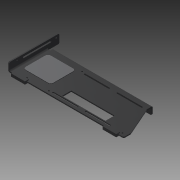
# Autodesk Inventor part: foot_plate
Saved by Autodesk Inventor 2015 (Build 190159000, 159)
## iProperties
Created: 2022-11-07
Part Number: foot_plate
Material: Generic
Document SubType Name: Modeling
Designer: Pavel Brodský
Density: 1 g/cm^3
Appearance: Default
Author: Pavel Brodský
Autodesk Inventor part; units mm, degrees
ref_plane "YZ Plane" through (0, 0, 0) normal (1, 0, 0) x (0, 1, 0)
ref_plane "XZ Plane" through (0, 0, 0) normal (0, 1, 0) x (-1, 0, 0)
ref_plane "XY Plane" through (0, 0, 0) normal (0, 0, 1) x (1, 0, 0)
sketch "Náčrt1" plane through (0, 0, 0) normal (0, 0, 1) x (1, 0, 0)
  line L0 (0, 0) -> (9, 0)
  line L1 (9, 0) -> (9, 12)
  line L2 (9, 12) -> (367, 12)
  line L3 (367, 12) -> (367, -10)
  line L4 (367, -10) -> (412, -113)
  line L5 (412, -113) -> (412, -138)
  line L6 (412, -138) -> (0, -138)
  line L7 (0, -138) -> (0, 0)
  arc A0 (145, -123) -> (145, -128) centre (145, -125.5) ccw
  arc A1 (233, -128) -> (233, -123) centre (233, -125.5) ccw
  line L8 (145, -123) -> (233, -123)
  line L9 (145, -128) -> (233, -128)
  arc A2 (263, -123) -> (263, -128) centre (263, -125.5) ccw
  arc A3 (351, -128) -> (351, -123) centre (351, -125.5) ccw
  line L10 (263, -123) -> (351, -123)
  line L11 (263, -128) -> (351, -128)
  arc A4 (145, -9) -> (145, -14) centre (145, -11.5) ccw
  arc A5 (233, -14) -> (233, -9) centre (233, -11.5) ccw
  line L12 (145, -9) -> (233, -9)
  line L13 (145, -14) -> (233, -14)
  arc A6 (263, -9) -> (263, -14) centre (263, -11.5) ccw
  arc A7 (351, -14) -> (351, -9) centre (351, -11.5) ccw
  line L14 (263, -9) -> (351, -9)
  line L15 (263, -14) -> (351, -14)
  line L16 (174, -86.99) -> (326, -86.99)
  line L17 (328, -88.99) -> (328, -117.99)
  line L18 (326, -119.99) -> (174, -119.99)
  line L19 (172, -117.99) -> (172, -88.99)
  circle A8 centre (397, -127) radius 2.5
  circle A9 centre (52.5, -127) radius 2.5
  circle A10 centre (132.5, -8) radius 2.5
  circle A11 centre (132.5, -128) radius 2.5
  arc A12 (174, -86.99) -> (172, -88.99) centre (174, -88.99) ccw
  arc A13 (172, -117.99) -> (174, -119.99) centre (174, -117.99) ccw
  arc A14 (328, -88.99) -> (326, -86.99) centre (326, -88.99) ccw
  arc A15 (326, -119.99) -> (328, -117.99) centre (326, -117.99) ccw
  point P0 (172, -86.99)
  point P1 (328, -86.99)
  dimension "d0" = 358
  dimension "d1" = 22
  dimension "d2" = 150
  dimension "d3" = 412
  dimension "d4" = 9
  dimension "d5" = 12
  dimension "d6" = 25
  dimension "d7" = 5
  dimension "d8" = 5
  dimension "d9" = 88
  dimension "d10" = 135
  dimension "d13" = 118
  dimension "d16" = 114
  dimension "d19" = 16
  dimension "d20" = 156
  dimension "d21" = 33
  dimension "d22" = 5.51
  dimension "d23" = 84
  dimension "d24" = 5
  dimension "d25" = 15
  dimension "d26" = 11
  dimension "d27" = 5
  dimension "d28" = 11
  dimension "d29" = 92.5
  dimension "d30" = 5
  dimension "d31" = 5
  dimension "d32" = 120
  dimension "d33" = 10
  dimension "d34" = 80
  dimension "d35" = 2
  constraints: 40 end point, 24 point on circle, 16 centre point, 11 tangent, 6 perpendicular, 4 point on line, 3 equal radius, 3 horizontal, 3 parallel, 1 collinear, 1 horizontal alignment, 1 vertical, 1 vertical alignment, 29 other
  measures "d0" distance of L1.end L2.end
  measures "d1" distance of L2.end L3.end
  measures "d2" distance between parallel lines of L6 L2
  measures "d3" distance of L5.end L6.end
  measures "d4" distance of L0.start L0.end
  measures "d5" distance of L0.end L1.end
  measures "d6" distance of L4.end L5.end
  measures "d7" diameter of A0
  measures "d8" diameter of A1
  measures "d9" distance of A1.centre A0.centre
  measures "d10" distance between parallel lines of L2 L8
  measures "d13" distance of L9.start L11.start
  measures "d16" distance of L9.start L13.start
  measures "d19" distance from line of A7.centre L3
  measures "d20" distance of point (172, -86.99) point (328, -86.99)
  measures "d21" distance between parallel lines of L18 L16
  measures "d22" distance from line of L18 A0.centre
  measures "d23" distance between parallel lines of L5 L17
  measures "d24" diameter of A8
  measures "d25" distance from line of L5 A8.centre
  measures "d26" distance from line of L6 A8.centre
  measures "d27" diameter of A9
  measures "d28" distance from line of L6 A9.centre
  measures "d29" horizontal distance of A9.centre A0.centre
  measures "d30" diameter of A10
  measures "d31" diameter of A11
  measures "d32" distance of A11.centre A10.centre
  measures "d33" distance from line of L6 A11.centre
  measures "d34" horizontal distance of A9.centre A11.centre
  measures "d35" radius of A12
extrude "Vysunutí1" add sketch "Náčrt1" along normal blind 4
sketch "Náčrt2" plane through (0, -138, 0) normal (-1, 0, 0) x (0, 0, 1)
  line L0 (0, 0) -> (32, 0)
  line L1 (32, 0) -> (32, 180)
  line L2 (32, 180) -> (0, 180)
  line L3 (0, 180) -> (0, 0)
  point P0 (0, 138)
  dimension "d38" = 32
  dimension "d39" = 180
  constraints: 8 end point, 2 parallel, 1 coincident, 1 horizontal, 1 perpendicular
  measures "d38" distance of L1.end L2.end
  measures "d39" distance between parallel lines of L0 L2
extrude "Vysunutí2" add sketch "Náčrt2" along normal blind 4
sketch "Náčrt4" plane through (9, 12, 0) normal (0, 1, 0) x (1, 0, 0)
  line L0 (0, -4) -> (358, -4)
  line L1 (358, -4) -> (358, 24)
  line L2 (358, 24) -> (0, 24)
  line L3 (0, 24) -> (0, -4)
  point P0 (-9, 0)
  dimension "d42" = 28
  constraints: 8 end point, 2 parallel, 1 coincident, 1 horizontal, 1 perpendicular
  measures "d42" distance between parallel lines of L0 L2
extrude "Vysunutí3" add sketch "Náčrt4" against normal blind 4
sketch "Náčrt6" plane through (0, 0, 4) normal (0, 0, 1) x (1, 0, 0)
  line L0 (27, -16) -> (107, -16)
  line L1 (117, -26) -> (117, -96)
  line L2 (107, -106) -> (27, -106)
  line L3 (17, -96) -> (17, -26)
  arc A0 (27, -16) -> (17, -26) centre (27, -26) ccw
  arc A1 (17, -96) -> (27, -106) centre (27, -96) ccw
  arc A2 (107, -106) -> (117, -96) centre (107, -96) ccw
  arc A3 (117, -26) -> (107, -16) centre (107, -26) ccw
  line L4 (0, -138) -> (412, -138) projected
  line L5 (172, -117.99) -> (172, -88.99) projected
  point P0 (0, 0)
  dimension "d62" = 10
  dimension "d63" = 100
  dimension "d64" = 90
  dimension "d65" = 32
  dimension "d66" = 55
  constraints: 8 end point, 8 point on circle, 8 tangent, 4 centre point, 3 equal radius, 2 parallel, 1 horizontal, 1 perpendicular
  measures "d62" radius of A0
  measures "d63" distance between parallel lines of L1 L3
  measures "d64" distance between parallel lines of L2 L0
  measures "d65" distance between parallel lines of L4 L2
  measures "d66" distance between parallel lines of L5 L1
extrude "Vysunutí5" add sketch "Náčrt6" along normal blind 1.5
sketch "Náčrt7" plane through (0, -138, 0) normal (1, 0, 0) x (0, 0, -1)
  circle A0 centre (-24, 28) radius 2.5
  circle A1 centre (-24, 169) radius 2.5
  arc A2 (-19, 148.5) -> (-24, 148.5) centre (-21.5, 148.5) ccw
  arc A3 (-24, 51.5) -> (-19, 51.5) centre (-21.5, 51.5) ccw
  line L0 (-32, 0) -> (-32, 180) projected
  line L1 (-24, 148.5) -> (-24, 51.5)
  line L2 (-19, 148.5) -> (-19, 51.5)
  line L3 (-32, 180) -> (0, 180) projected
  point P0 (0, 138)
  dimension "d69" = 5
  dimension "d70" = 5
  dimension "d71" = 8
  dimension "d72" = 11
  dimension "d73" = 28
  dimension "d74" = 5
  dimension "d75" = 5
  dimension "d76" = 97
  dimension "d77" = 31.5
  dimension "d78" = 8
  constraints: 4 centre point, 4 end point, 4 point on circle, 4 tangent, 2 vertical alignment
  measures "d69" diameter of A0
  measures "d70" diameter of A1
  measures "d71" distance from line of L0 A1.centre
  measures "d72" vertical distance of L0.end A1.centre
  measures "d73" vertical distance of L0.start A0.centre
  measures "d74" diameter of A2
  measures "d75" diameter of A3
  measures "d76" distance of A3.centre A2.centre
  measures "d77" distance from line of L3 A2.centre
  measures "d78" distance from line of L0.end L1
extrude "Vysunutí6" cut sketch "Náčrt7" against normal through all
fillet "Zaoblení2" radius 5 12 edges at (412, -138, 2) (412, -113, 2) (367, -10, 2) (367, 10, -24) (9, 10, -24) (-2, 42, 0) (-2, 42, 32) (-2, -138, 32) (0, -69, 4) (-4, -48, 0) (188, 12, 4) (188, 8, 0)
sketch "Náčrt8" plane through (0, 0, 4) normal (0, 0, 1) x (1, 0, 0)
  line L0 (13, -131) -> (63, -131)
  line L1 (63, -131) -> (63, -145)
  line L2 (63, -145) -> (13, -145)
  line L3 (13, -145) -> (13, -131)
  line L4 (343, -131) -> (392, -131)
  line L5 (392, -131) -> (392, -145)
  line L6 (392, -145) -> (343, -145)
  line L7 (343, -145) -> (343, -131)
  line L8 (412, -133) -> (412, -114.0446) projected
  line L9 (5, -138) -> (407, -138) projected
  point P0 (0, 0)
  dimension "d82" = 49
  dimension "d83" = 50
  dimension "d84" = 14
  dimension "d85" = 14
  dimension "d86" = 280
  dimension "d87" = 20
  dimension "d88" = 7
  constraints: 16 end point, 4 parallel, 2 horizontal, 2 perpendicular, 1 horizontal alignment
  measures "d82" distance of L5.end L6.end
  measures "d83" distance of L1.end L2.end
  measures "d84" distance of L0.end L1.end
  measures "d85" distance of L6.end L4.start
  measures "d86" distance between parallel lines of L7 L1
  measures "d87" distance between parallel lines of L5 L8
  measures "d88" distance between parallel lines of L6 L9
extrude "Vysunutí7" add sketch "Náčrt8" along normal blind 3 and the other way blind 7
equation "\"d8\" = d7"
equation "\"d27\" = d24"
equation "\"d28\" = d26"
equation "\"d31\" = d30"
equation "\"d70\" = d69"
equation "\"d75\" = d74"
equation "\"d84\" = d85"
